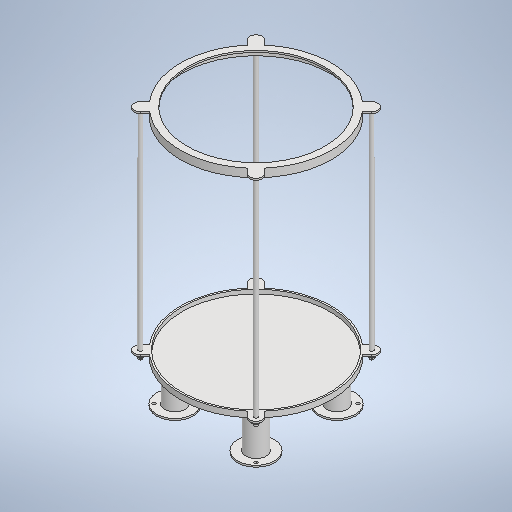
# Autodesk Inventor part: Peça2
Saved by Autodesk Inventor 2025 (Build 290162000, 162)
## iProperties
Created: 2026-10-05
Part Number: Peça2
Material: Genérico
Document SubType Name: Modeling
Designer: Projeto
Density: 1 g/cm^3
Appearance: Padrão
Author: Projeto
Autodesk Inventor part; units mm, degrees
ref_plane "YZ Plane" through (0, 0, 0) normal (1, 0, 0) x (0, 1, 0)
ref_plane "XZ Plane" through (0, 0, 0) normal (0, 1, 0) x (-1, 0, 0)
ref_plane "XY Plane" through (0, 0, 0) normal (0, 0, 1) x (1, 0, 0)
sketch "Esboço1" plane through (0, 0, 0) normal (0, 0, 1) x (1, 0, 0)
  line L0 (0, 0) -> (-90.25, 0)
  line L1 (-90.25, 0) -> (-90.25, 5)
  line L2 (-90.25, 5) -> (-92.25, 5)
  line L3 (-92.25, 5) -> (-92.25, -2)
  line L4 (-92.25, -2) -> (0, -2)
  line L5 (0, -2) -> (0, 0)
  line L6 (-90.25, 252) -> (-92.25, 252)
  line L7 (-92.25, 252) -> (-92.25, 262)
  line L8 (-92.25, 262) -> (-90.25, 262)
  line L9 (-90.25, 262) -> (-90.25, 252)
  line L10 (-90.25, 262) -> (-84, 262)
  line L11 (-84, 262) -> (-84, 260)
  line L12 (-84, 260) -> (-90.25, 260)
  dimension "d0" = 180.5
  dimension "d1" = 2
  dimension "d2" = 2
  dimension "d3" = 5
  dimension "d30" = 10
  dimension "d31" = 262
  dimension "d32" = 2
  dimension "d49" = 168
  constraints: 26 end point, 8 perpendicular, 3 horizontal, 2 parallel, 2 vertical alignment, 1 point on line
  measures "d0" diameter of L1 L5
  measures "d1" distance of L1.end L2.end
  measures "d2" distance between parallel lines of L4 L0
  measures "d3" distance between parallel lines of L0 L2
  measures "d30" distance of L6.end L7.end
  measures "d31" distance between parallel lines of L0 L8
  measures "d32" distance of L10.end L11.end
  measures "d49" diameter of L11 L5
revolve "Revolução1" add sketch "Esboço1" angle 360 about axis through (0, -2, 0) along (0, 1, 0)
sketch "Esboço2" plane through (0, -2, 0) normal (0, -1, 0) x (1, 0, 0)
  circle A0 centre (-49.497475, 49.497475) radius 12.5
  line L0 (-49.497475, 49.497475) -> (0, 0) construction
  line L1 (0, 0) -> (0, 92.25) construction
  circle A1 centre (0, 0) radius 92.25 construction
  dimension "d5" = 45
  dimension "d6" = 25
  dimension "d7" = 70
  constraints: 4 end point, 1 centre point, 1 vertical, 1 vertical alignment, 1 other
  measures "d5" angle of L0 L1
  measures "d6" diameter of A0
  measures "d7" distance of L0.start L0.end
extrude "Extrusão1" add sketch "Esboço2" along normal blind 50
sketch "Esboço3" plane through (-49.497475, -52, 49.497475) normal (0, -1, 0) x (1, 0, 0)
  circle A0 centre (0, 0) radius 12.5 construction
  circle A1 centre (0, 0) radius 22.5
  point P0 (49.497475, -49.497475)
  dimension "d10" = 45
  constraints: 1 centre point, 1 coincident
  measures "d10" diameter of A1
extrude "Extrusão2" add sketch "Esboço3" along normal blind 2
sketch "Esboço4" plane through (-49.497475, -54, 49.497475) normal (0, -1, 0) x (1, 0, 0)
  circle A0 centre (0, 0) radius 22.5 construction
  line L0 (0, 0) -> (0, 22.5) construction
  line L1 (0, 0) -> (-12.727922, 12.727922) construction
  point P0 (49.497475, -49.497475)
  dimension "d16" = 45
  dimension "d17" = 18
  constraints: 4 end point, 1 coincident, 1 vertical, 1 vertical alignment, 1 other
  measures "d16" angle of L1 L0
  measures "d17" distance of L0.start L1.end
hole "Furo1" at (-62.225397, -54, 62.225397) direction (0, 1, 0) diameter 4 depth 8 tip angle 118
sketch "Esboço5" plane through (0, 5, 0) normal (0, 1, 0) x (1, 0, 0)
  circle A0 centre (0, 0) radius 92.25
  line L0 (-92.25, 0) -> (0, 0) construction
  line L1 (0, 0) -> (-70.671516, -70.671516) construction
  line L2 (-75.974817, -65.368215) -> (-70.317963, -59.711361)
  line L3 (-65.368215, -75.974817) -> (-59.711361, -70.317963)
  arc A1 (-75.974817, -65.368215) -> (-65.368215, -75.974817) centre (-70.671516, -70.671516) ccw
  line L4 (-70.671516, -70.671516) -> (-75.974817, -75.974817) construction
  point P0 (0, 0)
  dimension "d26" = 15
  dimension "d28" = 8
  dimension "d29" = 45
  constraints: 11 end point, 6 point on circle, 2 parallel, 1 centre point, 1 coincident, 1 collinear, 1 horizontal, 1 tangent
  measures "d26" distance between parallel lines of L3 L2
  measures "d28" distance of L2.start L2.end
  measures "d29" angle of L1 L0
extrude "Extrusão3" add sketch "Esboço5" against normal blind 2 contours A0 L3 A1 L2
pattern_linear "Padrão retangular1" count 2 spacing 257 along (0, 1, 0) of "Extrusão3"
sketch "Esboço6" plane through (-70.671516, 260, 70.671516) normal (0, -1, 0) x (0.7071068, 0, -0.7071068)
  arc A0 (0, 7.5) -> (0, -7.5) centre (0, 0) ccw construction
  circle A1 centre (0, 0) radius 2.5
  point P0 (99.944616, 0)
  dimension "d39" = 5
  constraints: 1 centre point, 1 coincident
  measures "d39" diameter of A1
extrude "Extrusão4" add sketch "Esboço6" along normal blind 265
sketch "Esboço7" plane through (0, 3, 0) normal (0, -1, 0) x (1, 0, 0)
  circle A0 centre (-70.671516, 70.671516) radius 2.5 construction
  line L0 (-75.290318, 70.671516) -> (-72.980917, 74.671516)
  line L1 (-72.980917, 74.671516) -> (-68.362115, 74.671516)
  line L2 (-68.362115, 74.671516) -> (-66.052714, 70.671516)
  line L3 (-66.052714, 70.671516) -> (-68.362115, 66.671516)
  line L4 (-68.362115, 66.671516) -> (-72.980917, 66.671516)
  line L5 (-72.980917, 66.671516) -> (-75.290318, 70.671516)
  point P0 (0, 0)
  dimension "d42" = 8
  constraints: 12 end point, 1 coincident, 1 horizontal alignment, 13 other
  measures "d42" distance between parallel lines of L4 L1
extrude "Extrusão5" add sketch "Esboço7" along normal blind 5
chamfer "Chanfro1" distance 1 angle 45 7 edges at (-70.6715, -2, 74.6715) (-67.2074, -2, 72.6715) (-67.2074, -2, 68.6715) (-74.1356, -2, 72.6715) (-74.1356, -2, 68.6715) (-70.6715, -2, 66.6715) (-72.4393, -5, 72.4393)
fillet "Arredondamento1" radius 5.5 6 edges at (-68.6508, -1.5, 74.1715) (-72.6922, -1.5, 74.1715) (-74.713, -1.5, 70.6715) (-66.6301, -1.5, 70.6715) (-72.6922, -1.5, 67.1715) (-68.6508, -1.5, 67.1715)
pattern_circular "Padrão circular1" count 4 over 360 about axis through (0, 1.5, 0) along (0, 1, 0) of "Extrusão2", "Extrusão1", "Furo1", "Extrusão3", "Padrão retangular1", "Extrusão4", "Extrusão5", "Chanfro1", "Arredondamento1"
